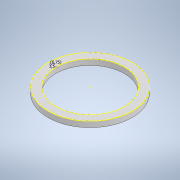
# Autodesk Inventor part: distantier priza
Saved by Autodesk Inventor 2022.6 (Build 266554000, 554)
## iProperties
Created: 2026-06-27
Part Number: distantier priza
Material: Generic
Document SubType Name: Modeling
Designer: Dragos Macovei
Density: 1 g/cm^3
Appearance: Default
Author: Dragos Macovei
Autodesk Inventor part; units mm, degrees
ref_plane "YZ Plane" through (0, 0, 0) normal (1, 0, 0) x (0, 1, 0)
ref_plane "XZ Plane" through (0, 0, 0) normal (0, 1, 0) x (-1, 0, 0)
ref_plane "XY Plane" through (0, 0, 0) normal (0, 0, 1) x (1, 0, 0)
sketch "Sketch1" plane through (0, 0, 0) normal (0, 1, 0) x (-1, 0, 0)
  circle A0 centre (0, 0) radius 29.75
  circle A1 centre (0, 0) radius 36.5
  dimension "d0" = 59.5
  dimension "d1" = 73
  constraints: 2 centre point, 2 coincident
  measures "d0" diameter of A0
  measures "d1" diameter of A1
extrude "Extrusion1" add sketch "Sketch1" along normal blind 5
sketch "Sketch2" plane through (0, 5, 0) normal (0, 1, 0) x (1, 0, 0)
  circle A0 centre (0, 0) radius 36.5 projected
  circle A1 centre (0, 0) radius 29.75 projected
sketch "Sketch3" plane through (0, 5, 0) normal (0, 1, 0) x (1, 0, 0)
  circle A0 centre (0, 0) radius 36.5 projected
  circle A1 centre (0, 0) radius 29.75 projected
  circle A2 centre (0, 0) radius 36.5 projected
  circle A3 centre (0, 0) radius 29.75 projected
  point P0 (-33.25, 0)
  point P1 (-29.75, 0)
  dimension "d5" = 6.75
  dimension "d6" = 3.5
  constraints: 1 horizontal alignment, 1 other
  measures "d5" radial gap between concentric circles of A1 A0
  measures "d6" distance of point (-29.75, 0) point (-33.25, 0)
body "Solid1"
